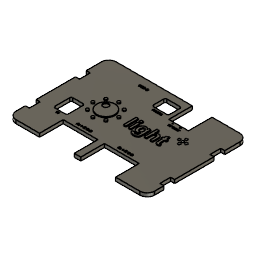
CoverCase (Autodesk Fusion 360 design; units mm, degrees)
part number: 2026-10-22-00-52-26-374
Autodesk Fusion 360 part; units mm, degrees
sketch "01 Contur capac 94 x 68 R5" plane through (0, 0, 0) normal (0, 0, 1) x (1, 0, 0)
  line L0 (5, 0) -> (89, 0)
  line L1 (94, 5) -> (94, 63)
  line L2 (89, 68) -> (5, 68)
  line L3 (0, 63) -> (0, 5)
  arc A0 (89, 0) -> (94, 5) centre (89, 5) ccw
  arc A1 (94, 63) -> (89, 68) centre (89, 63) ccw
  arc A2 (5, 68) -> (0, 63) centre (5, 63) ccw
  arc A3 (0, 5) -> (5, 0) centre (5, 5) ccw
extrude "01 Capac 2.4 mm" add sketch "01 Contur capac 94 x 68 R5" along normal blind 2.4
sketch "02 Decupaje borne" plane through (0, 0, 0) normal (0, 0, 1) x (1, 0, 0)
  line L0 (21, -1) -> (44.5, -1)
  line L1 (44.5, -1) -> (44.5, 16)
  line L2 (44.5, 16) -> (21, 16)
  line L3 (21, 16) -> (21, -1)
  line L4 (49, -1) -> (72.5, -1)
  line L5 (72.5, -1) -> (72.5, 16)
  line L6 (72.5, 16) -> (49, 16)
  line L7 (49, 16) -> (49, -1)
  line L8 (56.7, 52) -> (70, 52)
  line L9 (70, 52) -> (70, 69)
  line L10 (70, 69) -> (56.7, 69)
  line L11 (56.7, 69) -> (56.7, 52)
extrude "02 Decupaje borne (1)" cut sketch "02 Decupaje borne" along normal blind 3
sketch "03 Acces jumper" plane through (0, 0, 0) normal (0, 0, 1) x (1, 0, 0)
  line L0 (44, 54.3) -> (53, 54.3)
  line L1 (54, 55.3) -> (54, 62.3)
  line L2 (53, 63.3) -> (44, 63.3)
  line L3 (43, 62.3) -> (43, 55.3)
  arc A0 (53, 54.3) -> (54, 55.3) centre (53, 55.3) ccw
  arc A1 (54, 62.3) -> (53, 63.3) centre (53, 62.3) ccw
  arc A2 (44, 63.3) -> (43, 62.3) centre (44, 62.3) ccw
  arc A3 (43, 55.3) -> (44, 54.3) centre (44, 55.3) ccw
extrude "03 Acces jumper (1)" cut sketch "03 Acces jumper" along normal blind 3
sketch "04 Acces IR" plane through (0, 0, 0) normal (0, 0, 1) x (1, 0, 0)
  line L0 (11.36, 20.15) -> (18.36, 20.15)
  line L1 (19.36, 21.15) -> (19.36, 31.15)
  line L2 (18.36, 32.15) -> (11.36, 32.15)
  line L3 (10.36, 31.15) -> (10.36, 21.15)
  arc A0 (18.36, 20.15) -> (19.36, 21.15) centre (18.36, 21.15) ccw
  arc A1 (19.36, 31.15) -> (18.36, 32.15) centre (18.36, 31.15) ccw
  arc A2 (11.36, 32.15) -> (10.36, 31.15) centre (11.36, 31.15) ccw
  arc A3 (10.36, 21.15) -> (11.36, 20.15) centre (11.36, 21.15) ccw
extrude "04 Acces IR (1)" cut sketch "04 Acces IR" along normal blind 3
sketch "05 Orificii buzzer" plane through (0, 0, 0) normal (0, 0, 1) x (1, 0, 0)
  circle A0 centre (72.1, 43.7) radius 0.9
  circle A1 centre (74.5, 43.7) radius 0.9
  circle A2 centre (76.9, 43.7) radius 0.9
  circle A3 centre (74.5, 41.3) radius 0.9
  circle A4 centre (74.5, 46.1) radius 0.9
extrude "05 Orificii buzzer (1)" cut sketch "05 Orificii buzzer" along normal blind 3
sketch "06 Locasuri clips" plane through (0, 0, 0) normal (0, 0, 1) x (1, 0, 0)
  line L0 (-1, 11.4) -> (2.7, 11.4)
  line L1 (2.7, 11.4) -> (2.7, 18.6)
  line L2 (2.7, 18.6) -> (-1, 18.6)
  line L3 (-1, 18.6) -> (-1, 11.4)
  line L4 (-1, 45.4) -> (2.7, 45.4)
  line L5 (2.7, 45.4) -> (2.7, 52.6)
  line L6 (2.7, 52.6) -> (-1, 52.6)
  line L7 (-1, 52.6) -> (-1, 45.4)
  line L8 (91.3, 11.4) -> (95, 11.4)
  line L9 (95, 11.4) -> (95, 18.6)
  line L10 (95, 18.6) -> (91.3, 18.6)
  line L11 (91.3, 18.6) -> (91.3, 11.4)
  line L12 (91.3, 45.4) -> (95, 45.4)
  line L13 (95, 45.4) -> (95, 52.6)
  line L14 (95, 52.6) -> (91.3, 52.6)
  line L15 (91.3, 52.6) -> (91.3, 45.4)
extrude "06 Locasuri clips (1)" cut sketch "06 Locasuri clips" along normal blind 3
ref_plane "WorkPlane1" through (0, 0, 2.4) normal (0, 0, 1) x (1, 0, 0)
sketch "07 Marcaj A: + R G B" plane through (0, 0, 2.4) normal (0, 0, 1) x (1, 0, 0)
  line L0 (7.7007, 10.6552) -> (57.7007, 10.6552) construction
  line L1 (57.7007, 10.6552) -> (57.7007, 26.6552) construction
  line L2 (57.7007, 26.6552) -> (7.7007, 26.6552) construction
  line L3 (7.7007, 26.6552) -> (7.7007, 10.6552) construction
  dimension "d21" = 1.4316
  text T0 "A: + R G B" font "Arial" height 1.4316 bold align centre middle in box 50 x 16 at (7.7007, 10.6552) x (1, 0) y (0, 1) spacing 1 kerned
extrude "07 Marcaj A: + R G B (1)" cut sketch "07 Marcaj A: + R G B" against normal blind 0.35 text T0
ref_plane "WorkPlane2" through (0, 0, 2.4) normal (0, 0, 1) x (1, 0, 0)
sketch "07 Marcaj B: + R G B" plane through (0, 0, 2.4) normal (0, 0, 1) x (1, 0, 0)
  line L0 (35.7739, 10.6552) -> (85.7739, 10.6552) construction
  line L1 (85.7739, 10.6552) -> (85.7739, 26.6552) construction
  line L2 (85.7739, 26.6552) -> (35.7739, 26.6552) construction
  line L3 (35.7739, 26.6552) -> (35.7739, 10.6552) construction
  dimension "d29" = 1.4316
  text T0 "B: + R G B" font "Arial" height 1.4316 bold align centre middle in box 50 x 16 at (35.7739, 10.6552) x (1, 0) y (0, 1) spacing 1 kerned
extrude "07 Marcaj B: + R G B (1)" cut sketch "07 Marcaj B: + R G B" against normal blind 0.35 text T0
ref_plane "WorkPlane3" through (0, 0, 2.4) normal (0, 0, 1) x (1, 0, 0)
sketch "07 Marcaj 5V ONLY" plane through (0, 0, 2.4) normal (0, 0, 1) x (1, 0, 0)
  line L0 (38.3909, 40.7497) -> (88.3909, 40.7497) construction
  line L1 (88.3909, 40.7497) -> (88.3909, 56.7497) construction
  line L2 (88.3909, 56.7497) -> (38.3909, 56.7497) construction
  line L3 (38.3909, 56.7497) -> (38.3909, 40.7497) construction
  dimension "d37" = 1.2885
  dimension "d38" = 0
  text T0 "5V ONLY" font "Arial" height 1.2885 bold align centre middle in box 50 x 16 at (38.3909, 40.7497) x (1, 0) y (0, 1) spacing 1 kerned
extrude "07 Marcaj 5V ONLY (1)" cut sketch "07 Marcaj 5V ONLY" against normal blind 0.35 text T0
ref_plane "WorkPlane4" through (0, 0, 2.4) normal (0, 0, 1) x (1, 0, 0)
sketch "07 Marcaj -" plane through (0, 0, 2.4) normal (0, 0, 1) x (1, 0, 0)
  line L0 (35.4688, 42.6675) -> (85.4688, 42.6675) construction
  line L1 (85.4688, 42.6675) -> (85.4688, 58.6675) construction
  line L2 (85.4688, 58.6675) -> (35.4688, 58.6675) construction
  line L3 (35.4688, 58.6675) -> (35.4688, 42.6675) construction
  dimension "d45" = 1.4316
  text T0 "-" font "Arial" height 1.4316 bold align centre middle in box 50 x 16 at (35.4688, 42.6675) x (1, 0) y (0, 1) spacing 1 kerned
extrude "07 Marcaj - (1)" cut sketch "07 Marcaj -" against normal blind 0.35 text T0
ref_plane "WorkPlane5" through (0, 0, 2.4) normal (0, 0, 1) x (1, 0, 0)
sketch "07 Marcaj +" plane through (0, 0, 2.4) normal (0, 0, 1) x (1, 0, 0)
  line L0 (40.4995, 42.9429) -> (90.4995, 42.9429) construction
  line L1 (90.4995, 42.9429) -> (90.4995, 58.9429) construction
  line L2 (90.4995, 58.9429) -> (40.4995, 58.9429) construction
  line L3 (40.4995, 58.9429) -> (40.4995, 42.9429) construction
  dimension "d53" = 1.4316
  text T0 "+" font "Arial" height 1.4316 bold align centre middle in box 50 x 16 at (40.4995, 42.9429) x (1, 0) y (0, 1) spacing 1 kerned
extrude "07 Marcaj + (1)" cut sketch "07 Marcaj +" against normal blind 0.35 text T0
ref_plane "WorkPlane6" through (0, 0, 2.4) normal (0, 0, 1) x (1, 0, 0)
sketch "07 Marcaj USB-C" plane through (0, 0, 2.4) normal (0, 0, 1) x (1, 0, 0)
  line L0 (4.5205, 54.0552) -> (54.5205, 54.0552) construction
  line L1 (54.5205, 54.0552) -> (54.5205, 70.0552) construction
  line L2 (54.5205, 70.0552) -> (4.5205, 70.0552) construction
  line L3 (4.5205, 70.0552) -> (4.5205, 54.0552) construction
  dimension "d61" = 1.4316
  text T0 "USB-C" font "Arial" height 1.4316 bold align centre middle in box 50 x 16 at (4.5205, 54.0552) x (1, 0) y (0, 1) spacing 1 kerned
extrude "07 Marcaj USB-C (1)" cut sketch "07 Marcaj USB-C" against normal blind 0.35 text T0
ref_plane "WorkPlane7" through (0, 0, 2.4) normal (0, 0, 1) x (1, 0, 0)
sketch "07 Marcaj POWER" plane through (0, 0, 2.4) normal (0, 0, 1) x (1, 0, 0)
  line L0 (23.5573, 44.3469) -> (73.5573, 44.3469) construction
  line L1 (73.5573, 44.3469) -> (73.5573, 60.3469) construction
  line L2 (73.5573, 60.3469) -> (23.5573, 60.3469) construction
  line L3 (23.5573, 60.3469) -> (23.5573, 44.3469) construction
  dimension "d69" = 1.2169
  text T0 "POWER" font "Arial" height 1.2169 bold align centre middle in box 50 x 16 at (23.5573, 44.3469) x (1, 0) y (0, 1) spacing 1 kerned
extrude "07 Marcaj POWER (1)" cut sketch "07 Marcaj POWER" against normal blind 0.35 text T0
ref_plane "WorkPlane8" through (0, 0, 2.4) normal (0, 0, 1) x (1, 0, 0)
sketch "07 Marcaj IR" plane through (0, 0, 2.4) normal (0, 0, 1) x (1, 0, 0)
  line L0 (-10.0865, 10.5469) -> (39.9135, 10.5469) construction
  line L1 (39.9135, 10.5469) -> (39.9135, 26.5469) construction
  line L2 (39.9135, 26.5469) -> (-10.0865, 26.5469) construction
  line L3 (-10.0865, 26.5469) -> (-10.0865, 10.5469) construction
  dimension "d77" = 1.2169
  text T0 "IR" font "Arial" height 1.2169 bold align centre middle in box 50 x 16 at (-10.0865, 10.5469) x (1, 0) y (0, 1) spacing 1 kerned
extrude "07 Marcaj IR (1)" cut sketch "07 Marcaj IR" against normal blind 0.35 text T0
ref_plane "WorkPlane9" through (0, 0, 2.4) normal (0, 0, 1) x (1, 0, 0)
sketch "08 Logo Octoglow" plane through (0, 0, 2.4) normal (0, 0, 1) x (1, 0, 0)
  circle A0 centre (30, 36) radius 6.1645
  circle A1 centre (38.8064, 36) radius 0.9907
  circle A2 centre (36.2271, 42.2271) radius 0.9907
  circle A3 centre (30, 44.8064) radius 0.9907
  circle A4 centre (23.7729, 42.2271) radius 0.9907
  circle A5 centre (21.1936, 36) radius 0.9907
  circle A6 centre (23.7729, 29.7729) radius 0.9907
  circle A7 centre (30, 27.1936) radius 0.9907
  circle A8 centre (36.2271, 29.7729) radius 0.9907
extrude "08 Logo Octoglow (1)" add sketch "08 Logo Octoglow" along normal blind 0.6
ref_plane "WorkPlane10" through (0, 0, 2.4) normal (0, 0, 1) x (1, 0, 0)
sketch "09 Reflexie logo" plane through (0, 0, 2.4) normal (0, 0, 1) x (1, 0, 0)
  circle A0 centre (27.5342, 38.4658) radius 1.9814
extrude "09 Reflexie logo (1)" cut sketch "09 Reflexie logo" along normal blind 0.6
ref_plane "WorkPlane11" through (0, 0, 2.4) normal (0, 0, 1) x (1, 0, 0)
sketch "10 Text light in relief" plane through (0, 0, 2.4) normal (0, 0, 1) x (1, 0, 0)
  line L0 (45, 29.2627) -> (85, 29.2627) construction
  line L1 (85, 29.2627) -> (85, 45.2627) construction
  line L2 (85, 45.2627) -> (45, 45.2627) construction
  line L3 (45, 45.2627) -> (45, 29.2627) construction
  dimension "d93" = 8.5898
  text T0 "light" font "Arial" height 8.5898 bold align left middle in box 40 x 16 at (45, 29.2627) x (1, 0) y (0, 1) spacing 1 kerned
extrude "10 Text light in relief (1)" add sketch "10 Text light in relief" along normal blind 0.6 text T0
equation "Wall = 2.4 mm" comment "Octoglow nominal dimension"
equation "BaseHeight = 28 mm" comment "Octoglow nominal dimension"
equation "LidThickness = 2.4 mm" comment "Octoglow nominal dimension"
equation "LogoRelief = 0.6 mm" comment "Octoglow nominal dimension"
equation "d5 = LidThickness"
equation "d22 = 'A: + R G B'"
equation "d30 = 'B: + R G B'"
equation "d38 = '5V ONLY'"
equation "d46 = '-'"
equation "d54 = '+'"
equation "d62 = 'USB-C'"
equation "d70 = 'POWER'"
equation "d78 = 'IR'"
equation "d83 = LogoRelief"
equation "d94 = 'light'"
named bodies: "Octoglow_Capac_Clips"
